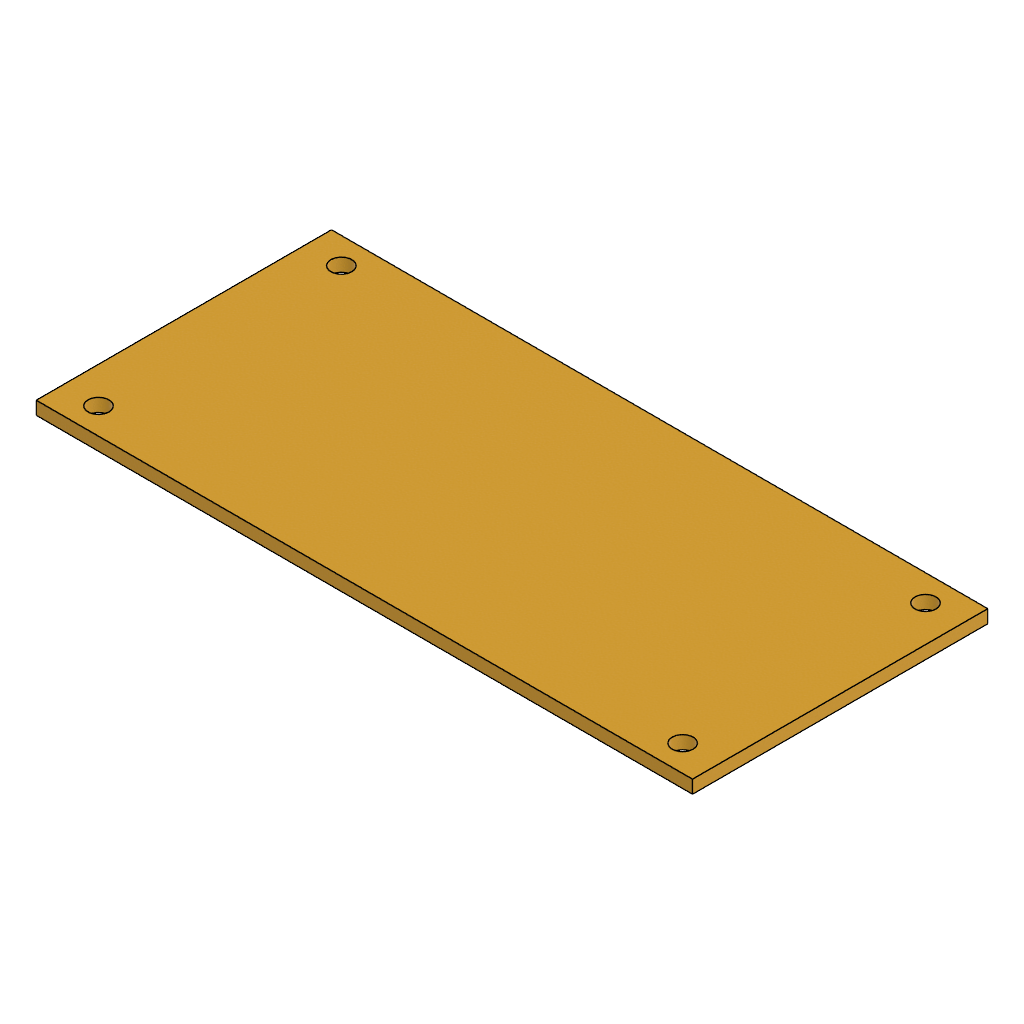
00-14 Perfboard Max232 support Placeholder (Autodesk Fusion 360 design; units mm, degrees)
part number: 2026-11-09-11-12-34-177
Autodesk Fusion 360 part; units mm, degrees
sketch "Sketch1" plane through (0, 0, 0) normal (0, 0, 1) x (1, 0, 0)
  line L0 (0, 0) -> (100, 0)
  line L1 (100, 0) -> (100, 45)
  line L2 (100, 45) -> (0, 45)
  line L3 (0, 45) -> (0, 0)
  circle A0 centre (94.5, 41) radius 1.6
  circle A1 centre (94.5, 4) radius 1.6
  circle A2 centre (5.5, 41) radius 1.6
  circle A3 centre (5.5, 4) radius 1.6
  dimension "d1" = 45
  dimension "d2" = 100
  dimension "d3" = 3.2
  dimension "d4" = 37
  dimension "d5" = 89
  dimension "d6" = 5.5
  dimension "d7" = 4
  constraint horizontal L0
  constraint vertical L1
  constraint horizontal L2
  constraint vertical L3
  constraint coincident L0.start L3.end
  constraint equal A0 A1
  constraint equal A1 A3
  constraint equal A2 A3
  constraint horizontal A0.centre A2.centre
  constraint vertical A0.centre A1.centre
  constraint horizontal A1.centre A3.centre
  constraint vertical A2.centre A3.centre
  measures "d1" distance of L0.start L2.end
  measures "d2" distance of L0.start L0.end
  measures "d3" diameter of A0
  measures "d4" distance of A0.centre A1.centre
  measures "d5" distance of A0.centre A2.centre
  measures "d6" distance of L1 A0.centre
  measures "d7" distance of L2 A0.centre
extrude "Extrude1" add sketch "Sketch1" along normal blind 2
